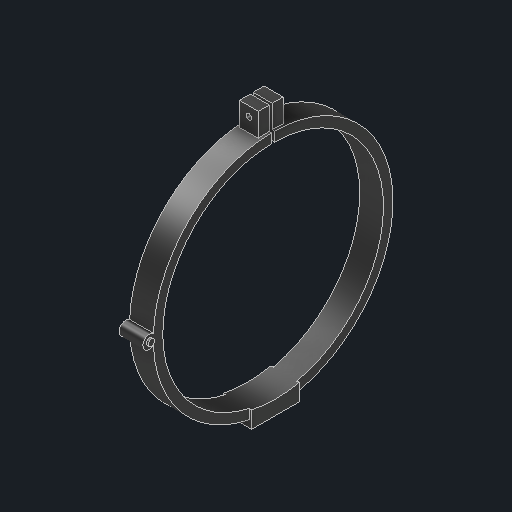
# Autodesk Inventor part: c8n_tube_ring
Saved by Autodesk Inventor 2027.1 (Build 311270010, 270A)
## iProperties
Created: 2026-11-04
Part Number: c8n_tube_ring
Material: Generic
Description: Hinged tube ring, 232 ID, 25 wide (x2)
Document SubType Name: Modeling
Designer: Claude (from photos)
Density: 1 g/cm^3
Appearance: Glossy - Black
Author: alexg
Autodesk Inventor part; units mm, degrees
ref_plane "Work Plane1" through (-12.5, 0, 0) normal (1, 0, 0) x (0, 1, 0)
sketch "Ring band sketch" plane through (-12.5, 0, 0) normal (1, 0, 0) x (0, 1, 0)
  circle A0 centre (0, 0) radius 126
  circle A1 centre (0, 0) radius 116
  constraints: 2 centre point
extrude "Ring band" add sketch "Ring band sketch" along normal blind 25
ref_plane "Work Plane2" through (0, -131, 0) normal (0, 1, 0) x (-1, 0, 0)
sketch "Base pad sketch" plane through (0, -131, 0) normal (0, 1, 0) x (-1, 0, 0)
  line L0 (15, -25) -> (-15, -25)
  line L1 (-15, -25) -> (-15, 25)
  line L2 (-15, 25) -> (15, 25)
  line L3 (15, 25) -> (15, -25)
  constraints: 8 end point, 2 parallel, 1 horizontal, 1 perpendicular
extrude "Base pad" add sketch "Base pad sketch" along normal blind 20
ref_plane "Work Plane3" through (0, 118, 0) normal (0, 1, 0) x (-1, 0, 0)
sketch "Clamp lugs sketch" plane through (0, 118, 0) normal (0, 1, 0) x (-1, 0, 0)
  line L0 (10, -13) -> (-10, -13)
  line L1 (-10, -13) -> (-10, 13)
  line L2 (-10, 13) -> (10, 13)
  line L3 (10, 13) -> (10, -13)
  constraints: 8 end point, 2 parallel, 1 horizontal, 1 perpendicular
extrude "Clamp lugs" add sketch "Clamp lugs sketch" along normal blind 32
ref_plane "Work Plane4" through (-12.5, 0, 0) normal (1, 0, 0) x (0, 1, 0)
sketch "Hinge knuckle sketch" plane through (-12.5, 0, 0) normal (1, 0, 0) x (0, 1, 0)
  circle A0 centre (0, 130) radius 7
  constraints: 1 centre point
extrude "Hinge knuckle" add sketch "Hinge knuckle sketch" along normal blind 25
ref_plane "Work Plane5" through (-20, 0, 0) normal (1, 0, 0) x (0, 1, 0)
sketch "Tube bore sketch" plane through (-20, 0, 0) normal (1, 0, 0) x (0, 1, 0)
  circle A0 centre (0, 0) radius 116
  constraints: 1 centre point
extrude "Tube bore" cut sketch "Tube bore sketch" along normal blind 40
ref_plane "Work Plane6" through (0, 100, 0) normal (0, 1, 0) x (-1, 0, 0)
sketch "Split sketch" plane through (0, 100, 0) normal (0, 1, 0) x (-1, 0, 0)
  line L0 (20, -1.5) -> (-20, -1.5)
  line L1 (-20, -1.5) -> (-20, 1.5)
  line L2 (-20, 1.5) -> (20, 1.5)
  line L3 (20, 1.5) -> (20, -1.5)
  constraints: 8 end point, 2 parallel, 1 horizontal, 1 perpendicular
extrude "Split" cut sketch "Split sketch" along normal blind 60
ref_plane "Work Plane7" through (0, 0, -20) normal (0, 0, 1) x (1, 0, 0)
sketch "Clamp screw hole sketch" plane through (0, 0, -20) normal (0, 0, 1) x (1, 0, 0)
  circle A0 centre (0, 140) radius 3
  constraints: 1 centre point
extrude "Clamp screw hole" cut sketch "Clamp screw hole sketch" along normal blind 40
ref_plane "Work Plane8" through (0, -131, 0) normal (0, 1, 0) x (-1, 0, 0)
sketch "Bar bolt hole sketch" plane through (0, -131, 0) normal (0, 1, 0) x (-1, 0, 0)
  circle A0 centre (0, 0) radius 3
  constraints: 1 centre point
extrude "Bar bolt hole" cut sketch "Bar bolt hole sketch" along normal blind 10
ref_plane "Work Plane9" through (12.5, 0, 0) normal (1, 0, 0) x (0, 1, 0)
sketch "Hinge pin head sketch" plane through (12.5, 0, 0) normal (1, 0, 0) x (0, 1, 0)
  circle A0 centre (0, 130) radius 3.5
  constraints: 1 centre point
extrude "Hinge pin head" add sketch "Hinge pin head sketch" along normal blind 2
body "Solid1"
